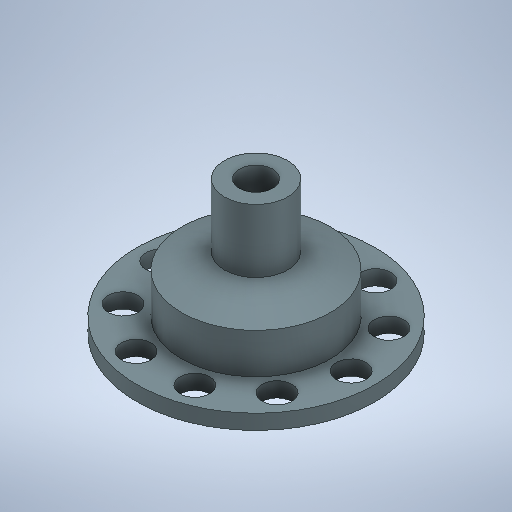
# Autodesk Inventor part: PIEZA 2 SEMANA 7
Saved by Autodesk Inventor 2025.1 (Build 291241000, 241)
## iProperties
Created: 2025-05-08
Part Number: PIEZA 2 SEMANA 7
Material: Plomo
Document SubType Name: Modeling
Designer: HP
Density: 11.34 g/cm^3
Appearance: Plomo
Author: HP
Autodesk Inventor part; units mm, degrees
ref_plane "YZ Plane" through (0, 0, 0) normal (1, 0, 0) x (0, 1, 0)
ref_plane "XZ Plane" through (0, 0, 0) normal (0, 1, 0) x (-1, 0, 0)
ref_plane "XY Plane" through (0, 0, 0) normal (0, 0, 1) x (1, 0, 0)
sketch "Boceto1" plane through (0, 0, 0) normal (1, 0, 0) x (0, 1, 0)
  line L0 (0, 0) -> (180, 0)
  line L1 (0, 0) -> (0, -80) construction
  line L2 (0, -80) -> (0, -160)
  line L3 (0, -160) -> (20, -160)
  line L4 (20, -160) -> (20, -100)
  line L5 (179.9777, -42.5) -> (94.9283, -42.5)
  line L6 (74, -100) -> (94.9283, -42.5)
  line L7 (110.397, 0) -> (111.6222, 3.3662)
  line L8 (179.9777, -22.5) -> (80.9241, -22.5)
  line L9 (80.9241, -22.5) -> (59.9958, -80)
  line L10 (179.9777, -22.5) -> (179.9777, -42.5)
  line L11 (0, -80) -> (59.9958, -80)
  line L12 (74, -100) -> (20, -100)
  dimension "d0" = 180
  dimension "d1" = 80
  dimension "d2" = 80
  dimension "d3" = 20
  dimension "d4" = 60
  dimension "d5" = 54
  dimension "d10" = 20
  constraints: 26 end point, 3 perpendicular, 3 vertical, 2 horizontal, 1 parallel, 1 point on line
  measures "d0" distance of L0.start L0.end
  measures "d1" distance of L0.start L1.end
  measures "d2" distance of L1.end L2.end
  measures "d3" distance of L2.end L3.end
  measures "d4" distance of L3.end L4.end
  measures "d5" distance of L4.end L6.start
  measures "d10" distance between parallel lines of L5 L8
revolve "Revolución1" add sketch "Boceto1" angle 360 about axis through (0, 0, 0) along (0, 1, 0)
sketch "Boceto2" plane through (0, 20, 0) normal (0, 1, 0) x (1, 0, 0)
  circle A0 centre (0, 0) radius 128 construction
  circle A1 centre (-128, 0) radius 20
  dimension "d12" = 256
  dimension "d13" = 40
  constraints: 1 centre point, 1 coincident, 1 horizontal alignment, 2 other
  measures "d13" diameter of A1
extrude "Extrusión1" cut sketch "Boceto2" against normal blind 49.75
pattern_circular "Patrón circular1" count 10 over 360 about axis through (0, 10, 0) along (0, 1, 0) of "Extrusión1"
